211501_P01_WALL-CAVITY-FILL-SIDE-LOWER-LH_CAD (Autodesk Fusion 360 design; units mm, degrees)
part number: 2026-11-01-01-09-27-023
description: WALL - CAVITY FILL - SIDE LOWER - LH | Vách trái - bông PET dưới | P01
part number: 211501
Autodesk Fusion 360 part; units mm, degrees
ref_plane "WorkPlane1" through (0, 0, 132.26) normal (0, 0, 1) x (1, 0, 0) in component "211501 WALL - CAVITY FILL - SIDE LOWER - LH"
sketch "SKETCH - FILL BAY 1" plane through (0, 0, 132.26) normal (0, 0, 1) x (1, 0, 0) in component "211501 WALL - CAVITY FILL - SIDE LOWER - LH"
  line L0 (-1244, -622.74) -> (-1204, -622.74)
  line L1 (-1204, -622.74) -> (-1204, -277.805)
  line L2 (-1204, -277.805) -> (-1244, -277.805)
  line L3 (-1244, -277.805) -> (-1244, -622.74)
  dimension "d167" = 40
  dimension "d168" = 344.935
  dimension "d169" = 1244
  dimension "d170" = 622.74
  constraint horizontal L0
  constraint vertical L1
  constraint horizontal L2
  constraint vertical L3
  measures "d167" horizontal distance of L0.start L0.end
  measures "d168" vertical distance of L0.start L2.end
  measures "d169" horizontal distance of origin L0.start
  measures "d170" vertical distance of origin L0.start
extrude "EXTRUDE - FILL BAY 1" add sketch "SKETCH - FILL BAY 1" along normal blind 1102.74 makes body 1 in component "211501 WALL - CAVITY FILL - SIDE LOWER - LH"
pattern_linear "PATTERN - FILL BAYS" count 3 spacing 364.935 along (0, 1, 0) of bodies 1 makes body 2 at (-1244, -27.8483, 499.84) makes body 3 at (-1244, 337.0867, 499.84) in component "211501 WALL - CAVITY FILL - SIDE LOWER - LH"
ref_plane "WorkPlane2" through (0, 0, 132.26) normal (0, 0, 1) x (1, 0, 0) in component "211501 WALL - CAVITY FILL - SIDE LOWER - LH"
sketch "SKETCH - FILL BAY LAST" plane through (0, 0, 132.26) normal (0, 0, 1) x (1, 0, 0) in component "211501 WALL - CAVITY FILL - SIDE LOWER - LH"
  line L0 (-1244, 472.065) -> (-1204, 472.065)
  line L1 (-1204, 472.065) -> (-1204, 807)
  line L2 (-1204, 807) -> (-1244, 807)
  line L3 (-1244, 807) -> (-1244, 472.065)
  dimension "d179" = 40
  dimension "d180" = 334.935
  dimension "d181" = 1244
  dimension "d182" = 472.065
  constraint horizontal L0
  constraint vertical L1
  constraint horizontal L2
  constraint vertical L3
  measures "d179" horizontal distance of L0.start L0.end
  measures "d180" vertical distance of L0.start L2.end
  measures "d181" horizontal distance of origin L0.start
  measures "d182" vertical distance of origin L0.start
extrude "EXTRUDE - FILL BAY LAST" add sketch "SKETCH - FILL BAY LAST" along normal blind 1102.74 separate body makes body 4 in component "211501 WALL - CAVITY FILL - SIDE LOWER - LH"
ref_plane "WorkPlane3" through (0, 0, 132.26) normal (0, 0, 1) x (1, 0, 0) in component "211501 WALL - CAVITY FILL - SIDE LOWER - LH"
sketch "SKETCH - FILL POCKET BOTTOM BOLT 1" plane through (0, 0, 132.26) normal (0, 0, 1) x (1, 0, 0) in component "211501 WALL - CAVITY FILL - SIDE LOWER - LH"
  line L0 (-1244, -452.74) -> (-1204, -452.74)
  line L1 (-1204, -452.74) -> (-1204, -392.74)
  line L2 (-1204, -392.74) -> (-1244, -392.74)
  line L3 (-1244, -392.74) -> (-1244, -452.74)
  dimension "d187" = 40
  dimension "d188" = 60
  dimension "d189" = 1244
  dimension "d190" = 452.74
  constraint horizontal L0
  constraint vertical L1
  constraint horizontal L2
  constraint vertical L3
  measures "d187" horizontal distance of L0.start L0.end
  measures "d188" vertical distance of L0.start L2.end
  measures "d189" horizontal distance of origin L0.start
  measures "d190" vertical distance of origin L0.start
extrude "CUT - FILL POCKET BOTTOM BOLT 1" cut sketch "SKETCH - FILL POCKET BOTTOM BOLT 1" along normal blind 60 bodies 1 in component "211501 WALL - CAVITY FILL - SIDE LOWER - LH"
ref_plane "WorkPlane4" through (0, 0, 132.26) normal (0, 0, 1) x (1, 0, 0) in component "211501 WALL - CAVITY FILL - SIDE LOWER - LH"
sketch "SKETCH - FILL POCKET BOTTOM BOLT 2" plane through (0, 0, 132.26) normal (0, 0, 1) x (1, 0, 0) in component "211501 WALL - CAVITY FILL - SIDE LOWER - LH"
  line L0 (-1244, -101.8267) -> (-1204, -101.8267)
  line L1 (-1204, -101.8267) -> (-1204, -41.8267)
  line L2 (-1204, -41.8267) -> (-1244, -41.8267)
  line L3 (-1244, -41.8267) -> (-1244, -101.8267)
  dimension "d195" = 40
  dimension "d196" = 60
  dimension "d197" = 1244
  dimension "d198" = 101.8267
  constraint horizontal L0
  constraint vertical L1
  constraint horizontal L2
  constraint vertical L3
  measures "d195" horizontal distance of L0.start L0.end
  measures "d196" vertical distance of L0.start L2.end
  measures "d197" horizontal distance of origin L0.start
  measures "d198" vertical distance of origin L0.start
extrude "CUT - FILL POCKET BOTTOM BOLT 2" cut sketch "SKETCH - FILL POCKET BOTTOM BOLT 2" along normal blind 60 bodies 2 in component "211501 WALL - CAVITY FILL - SIDE LOWER - LH"
ref_plane "WorkPlane5" through (0, 0, 132.26) normal (0, 0, 1) x (1, 0, 0) in component "211501 WALL - CAVITY FILL - SIDE LOWER - LH"
sketch "SKETCH - FILL POCKET BOTTOM BOLT 3" plane through (0, 0, 132.26) normal (0, 0, 1) x (1, 0, 0) in component "211501 WALL - CAVITY FILL - SIDE LOWER - LH"
  line L0 (-1244, 249.0867) -> (-1204, 249.0867)
  line L1 (-1204, 249.0867) -> (-1204, 309.0867)
  line L2 (-1204, 309.0867) -> (-1244, 309.0867)
  line L3 (-1244, 309.0867) -> (-1244, 249.0867)
  dimension "d203" = 40
  dimension "d204" = 60
  dimension "d205" = 1244
  dimension "d206" = 249.0867
  constraint horizontal L0
  constraint vertical L1
  constraint horizontal L2
  constraint vertical L3
  measures "d203" horizontal distance of L0.start L0.end
  measures "d204" vertical distance of L0.start L2.end
  measures "d205" horizontal distance of origin L0.start
  measures "d206" vertical distance of origin L0.start
extrude "CUT - FILL POCKET BOTTOM BOLT 3" cut sketch "SKETCH - FILL POCKET BOTTOM BOLT 3" along normal blind 60 bodies 3 in component "211501 WALL - CAVITY FILL - SIDE LOWER - LH"
ref_plane "WorkPlane6" through (0, 0, 132.26) normal (0, 0, 1) x (1, 0, 0) in component "211501 WALL - CAVITY FILL - SIDE LOWER - LH"
sketch "SKETCH - FILL POCKET BOTTOM BOLT 4" plane through (0, 0, 132.26) normal (0, 0, 1) x (1, 0, 0) in component "211501 WALL - CAVITY FILL - SIDE LOWER - LH"
  line L0 (-1244, 600) -> (-1204, 600)
  line L1 (-1204, 600) -> (-1204, 660)
  line L2 (-1204, 660) -> (-1244, 660)
  line L3 (-1244, 660) -> (-1244, 600)
  dimension "d211" = 40
  dimension "d212" = 60
  dimension "d213" = 1244
  dimension "d214" = 600
  constraint horizontal L0
  constraint vertical L1
  constraint horizontal L2
  constraint vertical L3
  measures "d211" horizontal distance of L0.start L0.end
  measures "d212" vertical distance of L0.start L2.end
  measures "d213" horizontal distance of origin L0.start
  measures "d214" vertical distance of origin L0.start
extrude "CUT - FILL POCKET BOTTOM BOLT 4" cut sketch "SKETCH - FILL POCKET BOTTOM BOLT 4" along normal blind 60 bodies 4 in component "211501 WALL - CAVITY FILL - SIDE LOWER - LH"
ref_plane "WorkPlane7" through (0, 0, 302.26) normal (0, 0, 1) x (1, 0, 0) in component "211501 WALL - CAVITY FILL - SIDE LOWER - LH"
sketch "SKETCH - FILL POCKET DECOR BOLT 1" plane through (0, 0, 302.26) normal (0, 0, 1) x (1, 0, 0) in component "211501 WALL - CAVITY FILL - SIDE LOWER - LH"
  line L0 (-1244, -622.74) -> (-1204, -622.74)
  line L1 (-1204, -622.74) -> (-1204, -562.74)
  line L2 (-1204, -562.74) -> (-1244, -562.74)
  line L3 (-1244, -562.74) -> (-1244, -622.74)
  dimension "d219" = 40
  dimension "d220" = 60
  dimension "d221" = 1244
  dimension "d222" = 622.74
  constraint horizontal L0
  constraint vertical L1
  constraint horizontal L2
  constraint vertical L3
  measures "d219" horizontal distance of L0.start L0.end
  measures "d220" vertical distance of L0.start L2.end
  measures "d221" horizontal distance of origin L0.start
  measures "d222" vertical distance of origin L0.start
extrude "CUT - FILL POCKET DECOR BOLT 1" cut sketch "SKETCH - FILL POCKET DECOR BOLT 1" along normal blind 60 bodies 1 in component "211501 WALL - CAVITY FILL - SIDE LOWER - LH"
ref_plane "WorkPlane8" through (0, 0, 653.63) normal (0, 0, 1) x (1, 0, 0) in component "211501 WALL - CAVITY FILL - SIDE LOWER - LH"
sketch "SKETCH - FILL POCKET DECOR BOLT 2" plane through (0, 0, 653.63) normal (0, 0, 1) x (1, 0, 0) in component "211501 WALL - CAVITY FILL - SIDE LOWER - LH"
  line L0 (-1244, -622.74) -> (-1204, -622.74)
  line L1 (-1204, -622.74) -> (-1204, -562.74)
  line L2 (-1204, -562.74) -> (-1244, -562.74)
  line L3 (-1244, -562.74) -> (-1244, -622.74)
  dimension "d227" = 40
  dimension "d228" = 60
  dimension "d229" = 1244
  dimension "d230" = 622.74
  constraint horizontal L0
  constraint vertical L1
  constraint horizontal L2
  constraint vertical L3
  measures "d227" horizontal distance of L0.start L0.end
  measures "d228" vertical distance of L0.start L2.end
  measures "d229" horizontal distance of origin L0.start
  measures "d230" vertical distance of origin L0.start
extrude "CUT - FILL POCKET DECOR BOLT 2" cut sketch "SKETCH - FILL POCKET DECOR BOLT 2" along normal blind 60 bodies 1 in component "211501 WALL - CAVITY FILL - SIDE LOWER - LH"
ref_plane "WorkPlane9" through (0, 0, 1005) normal (0, 0, 1) x (1, 0, 0) in component "211501 WALL - CAVITY FILL - SIDE LOWER - LH"
sketch "SKETCH - FILL POCKET DECOR BOLT 3" plane through (0, 0, 1005) normal (0, 0, 1) x (1, 0, 0) in component "211501 WALL - CAVITY FILL - SIDE LOWER - LH"
  line L0 (-1244, -622.74) -> (-1204, -622.74)
  line L1 (-1204, -622.74) -> (-1204, -562.74)
  line L2 (-1204, -562.74) -> (-1244, -562.74)
  line L3 (-1244, -562.74) -> (-1244, -622.74)
  dimension "d235" = 40
  dimension "d236" = 60
  dimension "d237" = 1244
  dimension "d238" = 622.74
  constraint horizontal L0
  constraint vertical L1
  constraint horizontal L2
  constraint vertical L3
  measures "d235" horizontal distance of L0.start L0.end
  measures "d236" vertical distance of L0.start L2.end
  measures "d237" horizontal distance of origin L0.start
  measures "d238" vertical distance of origin L0.start
extrude "CUT - FILL POCKET DECOR BOLT 3" cut sketch "SKETCH - FILL POCKET DECOR BOLT 3" along normal blind 60 bodies 1 in component "211501 WALL - CAVITY FILL - SIDE LOWER - LH"
component "211501 WALL - CAVITY FILL - SIDE LOWER - LH" placed x (1, 0, 0) y (0, 1, 0) z (0, 0, 1) at (0, 0, 0)
equation "pod_w_Ref = 2500 mm" comment "DECIDED: D-01; conventions s4 (X = +-1250)"
equation "pod_d_Ref = 1700 mm" comment "DECIDED: D-01; conventions s4 (Y = +-850)"
equation "pod_h_Ref = 2400 mm" comment "DECIDED: D-21 (room floor to roof skin top)"
equation "glide_h_Ref = 10 mm" comment "ASSUMPTION: layout study inputs.py glide_h"
equation "band_h_Ref = 100 mm" comment "SOURCE: layout study B1 list B-BAND 100x40; inputs.py base_h"
equation "outer_t_Ref = skin_t_Ref + bond_t_Ref + frame_t_Ref" comment "DECIDED: PM ruling 2026-10-31: ACP 3 + bond line 3 + frame 40, walls and ceiling (was 43)"
equation "cav_gap_Ref = 4 mm" comment "DECIDED: D-16, D-42: the gap between the outer panel and the lining cassette in the wall and ceiling stack"
equation "cass_t_Ref = 34 mm" comment "SOURCE: layout study B1 final list L-CASS 34 (tray + 25 gap + felt 9)"
equation "stack_t_Ref = outer_t_Ref + cav_gap_Ref + cass_t_Ref" comment "CALCULATION: D-16, D-42 stack, walls and ceiling: outer panel + cavity gap + cassette (PM ruling 2026-10-31 on outer_t)"
equation "wall_depth_Ref = 1495 mm" comment "DECIDED: PM ruling pass C: side walls start at the decor back plate (Y -645), as v1 (1496)"
equation "lin_gap_Ref = 4 mm" comment "ASSUMPTION: PM ruling pass C: gap above the upper side linings so they stay floating (= the 4 mm stack gap)"
equation "seam_gap_Ref = 2.26 mm" comment "DECIDED: PM ruling 2026-10-31 (Mechanical Checker F-001, F-005): the Joints Engineer's 2.26 mm at all nine site seam types, set by a metal stop (1.5 stop washer + 0.76 rivnut head; joints register section 2.8)"
equation "wall_z0_Ref = glide_h_Ref + band_h_Ref" comment "CALCULATION: base band top: glides + band"
equation "panel_z0_Ref = wall_z0_Ref + seam_gap_Ref" comment "CALCULATION: walls stand one seam_gap above the band top (joints register 2.8, IF-01)"
equation "wall_h_Ref = pod_h_Ref - wall_z0_Ref" comment "CALCULATION: 2290 = layout study v2_model wall_h"
equation "side_h_Ref = ( wall_h_Ref - 2 * seam_gap_Ref ) / 2" comment "CALCULATION: D-23: 2 sheets per side wall; the gap on the band and the horizontal seam (joints register 2.8)"
equation "back_oh_Ref = pod_h_Ref - outer_t_Ref - seam_gap_Ref - panel_z0_Ref" comment "CALCULATION: PM ruling 2026-10-31 (pass D, F-004): the back outer frames run up to the ceiling frame (pod_h - outer_t), less the seam_gap under it, closing the slot at the back top edge"
equation "back_ph_Ref = ( back_oh_Ref - seam_gap_Ref ) / 2" comment "CALCULATION: D-23: 4 sheets on the back, two equal rows with one seam_gap between them (joints register 2.8); the lower back linings match the lower row, as on the side walls"
equation "n_base_bolt_Ref = 4" comment "DECIDED: PM ruling 2026-10-31, J-BASE-01: bolts per panel along the band, evenly spaced"
equation "skin_t_Ref = 3 mm" comment "DECIDED: ACP skin, walls and ceiling (D-16; PM ruling 2026-10-31 on outer_t)"
equation "bond_t_Ref = 3 mm" comment "DECIDED: bond line between the ACP and the frame (PM ruling 2026-10-31 on outer_t)"
equation "frame_t_Ref = 40 mm" comment "DECIDED: aluminium frame tube depth, walls and ceiling (PM ruling 2026-10-31 on outer_t)"
equation "bolt_edge_inset_Ref = 220 mm" comment "DECIDED: PM ruling 2026-10-31: on every bolted edge the end bolts sit this far in from each panel end (the FRAME end, where the bolts go), the rest evenly spaced"
equation "spigot_inset_Ref = 100 mm" comment "DECIDED: PM ruling 2026-10-31: locating spigots this far in from each panel end (round hole at one end, slot at the other)"
equation "ceil_bolt_z_Ref = pod_h_Ref - outer_t_Ref + frame_t_Ref / 2" comment "DECIDED: PM ruling 2026-10-31, J-CEIL-01 wall to ceiling: the bolt line on the ceiling frame's centre (Z 2374)"
equation "pod_w = pod_w_Ref" comment "LINKED: pod_w_Ref, derived from 100000_P04_POD-SKELETON_CAD v4 (skeleton is the single source)"
equation "pod_d = pod_d_Ref" comment "LINKED: pod_d_Ref, derived from 100000_P04_POD-SKELETON_CAD v4 (skeleton is the single source)"
equation "pod_h = pod_h_Ref" comment "LINKED: pod_h_Ref, derived from 100000_P04_POD-SKELETON_CAD v4 (skeleton is the single source)"
equation "wall_depth = wall_depth_Ref" comment "LINKED: wall_depth_Ref, derived from 100000_P04_POD-SKELETON_CAD v4 (skeleton is the single source)"
equation "wall_z0 = wall_z0_Ref" comment "LINKED: wall_z0_Ref, derived from 100000_P04_POD-SKELETON_CAD v4 (skeleton is the single source)"
equation "panel_z0 = panel_z0_Ref" comment "LINKED: panel_z0_Ref, derived from 100000_P04_POD-SKELETON_CAD v4 (skeleton is the single source)"
equation "side_h = side_h_Ref" comment "LINKED: side_h_Ref, derived from 100000_P04_POD-SKELETON_CAD v4 (skeleton is the single source)"
equation "back_ph = back_ph_Ref" comment "LINKED: back_ph_Ref, derived from 100000_P04_POD-SKELETON_CAD v4 (skeleton is the single source)"
equation "stack_t = stack_t_Ref" comment "LINKED: stack_t_Ref, derived from 100000_P04_POD-SKELETON_CAD v4 (skeleton is the single source)"
equation "outer_t = outer_t_Ref" comment "LINKED: outer_t_Ref, derived from 100000_P04_POD-SKELETON_CAD v4 (skeleton is the single source)"
equation "cass_t = cass_t_Ref" comment "LINKED: cass_t_Ref, derived from 100000_P04_POD-SKELETON_CAD v4 (skeleton is the single source)"
equation "lin_gap = lin_gap_Ref" comment "LINKED: lin_gap_Ref, derived from 100000_P04_POD-SKELETON_CAD v4 (skeleton is the single source)"
equation "seam_gap = seam_gap_Ref" comment "LINKED: seam_gap_Ref, derived from 100000_P04_POD-SKELETON_CAD v4 (skeleton is the single source)"
equation "skin_t = skin_t_Ref" comment "LINKED: skin_t_Ref, derived from 100000_P04_POD-SKELETON_CAD v4 (skeleton is the single source)"
equation "bond_t = bond_t_Ref" comment "LINKED: bond_t_Ref, derived from 100000_P04_POD-SKELETON_CAD v4 (skeleton is the single source)"
equation "bolt_edge_inset = bolt_edge_inset_Ref" comment "LINKED: bolt_edge_inset_Ref, derived from 100000_P04_POD-SKELETON_CAD v4 (skeleton is the single source)"
equation "spigot_inset = spigot_inset_Ref" comment "LINKED: spigot_inset_Ref, derived from 100000_P04_POD-SKELETON_CAD v4 (skeleton is the single source)"
equation "n_base_bolt = n_base_bolt_Ref" comment "LINKED: n_base_bolt_Ref, derived from 100000_P04_POD-SKELETON_CAD v4 (skeleton is the single source)"
equation "ceil_bolt_z = ceil_bolt_z_Ref" comment "LINKED: ceil_bolt_z_Ref, derived from 100000_P04_POD-SKELETON_CAD v4 (skeleton is the single source)"
equation "tube_w = 20 mm" comment "CONFIRMED: D-34, D-54: aluminium tube 20 x 40 x 1.2; the 20 mm face carries the skin, so the 40 mm runs through the wall (outer_t = ACP 3 + frame 40). The joint register may turn it for the bond width (HOLD)"
equation "tube_d = outer_t - skin_t - bond_t" comment "CALCULATION: frame depth = outer panel 46 - skin 3 - bond 3 = 40 (D-34)"
equation "tube_t = 1.2 mm" comment "CONFIRMED: D-34, D-54, D-85: perimeter members (rails, front and back stiles) keep the 1.2 mm wall; they carry the rivnuts (grip check passed)"
equation "stud_t = 1.0 mm" comment "CONFIRMED: D-85 (weight): intermediate studs at a 1.0 mm wall; they carry no rivnut, only the skin's bond line"
equation "stile_pitch_max = 400 mm" comment "CONFIRMED: D-16, D-34: members 400 mm apart or less, to keep the ACP flat"
equation "pnl_len = wall_depth - seam_gap" comment "CALCULATION: D-49 depth 1495 less the 2.26 gap at the decor back plate (PM ruling on F-008): 1492.74"
equation "pnl_h = side_h" comment "CALCULATION: skeleton side_h: 2 sheets per side wall (D-23) with the seam gaps"
equation "skin_ret = outer_t - skin_t" comment "ASSUMPTION: back return of the side skin: covers the frame's back end at the corner, where the side skin covers the back panel's edge (D-55; sample drawing D04). V-groove and fold per the ACP maker (HOLD H16)"
equation "skin_setback = 0 mm" comment "ASSUMPTION: skin edge set back from the frame's top and bottom edges: 0, so the outside reveal equals the 2.26 seam gap (D-23: crisp, aligned reveals; joints register 2.8 leaves the setback to the WALL drawing)"
equation "frm_len = pnl_len - skin_t" comment "CALCULATION: the frame stops at the inside of the skin's back return"
equation "frm_h = pnl_h" comment "ASSUMPTION: the frame fills the skeleton envelope height; seam and base gasket gaps are set by the joint register (HOLD)"
equation "corner_w = 40 mm" comment "CONFIRMED: the side panel's back member is 40 x 40 x 1.2 (PM ruling on the joints register, item 3, 2026-10-31; register F2, FR-06): the back corner joint needs a 37+ mm overlap for the rivnut and the bolt"
equation "stile_n_mid = ceil(( frm_len - tube_w / 2 - corner_w / 2 ) / stile_pitch_max) - 1" comment "CALCULATION: intermediate stiles so that no stile pitch (centre to centre) exceeds stile_pitch_max"
equation "stile_pitch = ( frm_len - tube_w / 2 - corner_w / 2 ) / ( stile_n_mid + 1 )" comment "CALCULATION: equal stile pitch, centre to centre, from the front stile to the 40 mm back stile"
equation "top_h = tube_w" comment "CALCULATION: top member height: 20 on a lower panel; 40 x 40 on an upper panel, where the ceiling bolts in (PM ruling R-J3, joints register FR-06)"
equation "stile_len = frm_h - tube_w - top_h" comment "CALCULATION: stiles fit between the full-length rails (butt joints)"
equation "ceil_bolt_dz = pod_h - ceil_bolt_z" comment "CALCULATION: J-CEIL-01 side bolts on the ceiling frame tube's centre: the skeleton's ceil_bolt_z, Z 2374 on P04 (joints register R-J15, FR-07)"
equation "fill_t = tube_d" comment "CALCULATION: 40 mm PET fill fills the frame depth (D-34; layout study 40 mm)"
equation "bolt_d = 7 mm" comment "CONFIRMED: PM ruling on F-009: bolt holes 7.0 (0.51 float), position tolerance 0.4 (+-0.2) from the spigot hole, CNC or drill jig (joints register FR-02)"
equation "access_d = 19 mm" comment "CALCULATION: register FR-03: passes the 18 mm head washer (ISO 7093-1, R-J10), the M6 head and the 5 mm key; holds the grommet retainer (H-02)"
equation "bolt_line_y = pod_d / 2 - skin_t - bond_t - tube_d / 2" comment "CONFIRMED: J-WALL-02 bolt line on the back panel's tube centre, Y 824 (joints register R-J15, FR-07)"
equation "rivnut_d = 9.53 mm" comment "SOURCE: Sherex CAH3-610-4.2 hole 9.53 +0.10 (HW-SEL A5; register H-03)"
equation "spigot_d = 8.5 mm" comment "ASSUMPTION: register FR-05: hole for the 8 mm locating spigot H-05"
equation "spigot_slot = 14 mm" comment "ASSUMPTION: register FR-05: slot length for the second spigot"
equation "spigot_edge = spigot_inset" comment "CALCULATION: the skeleton's spigot_inset: spigots 100 from each end of the edge (PM ruling 2026-10-31, R-J13)"
equation "bolt_edge = bolt_edge_inset" comment "CALCULATION: the skeleton's bolt_edge_inset: end bolts 220 in from the panel's ends, evenly spaced, every bolt 30 or more from any stile (PM ruling 2026-10-31, R-J14)"
equation "n_side_jnt = 3" comment "SOURCE: register J-WALL-02, J-FRONT-01: 3 bolts up each side panel"
equation "side_jnt_pitch = ( pnl_h - 2 * bolt_edge ) / ( n_side_jnt - 1 )" comment "CALCULATION: equal pitch of the 3 bolts up the corner and decor joints"
equation "pocket_w = 60 mm" comment "ASSUMPTION: register FR-10: fill left out 60 x 60 next to each bolt for the key"
equation "corner_z0 = panel_z0" comment "CALCULATION: bottom of the back panel row this side panel meets at the corner (B1/B2 or B3/B4, skeleton P04)"
equation "corner_bolt_pitch = ( back_ph - 2 * bolt_edge ) / ( n_side_jnt - 1 )" comment "CALCULATION: J-WALL-02 bolts run along the back panel's edge: 220, 559.31, 898.61 on its 1118.61 (joints register 2.9)"
equation "n_len_bolt = n_base_bolt" comment "CALCULATION: the skeleton's n_base_bolt (4): the same count on J-WALL-01 and the J-CEIL-01 side edges (register 2.9)"
equation "ceil_bolt_pitch = ( wall_depth - 2 * bolt_edge ) / ( n_len_bolt - 1 )" comment "CALCULATION: J-CEIL-01 side edge: 4 bolts along the ceiling's 1495 from Y -645 (its front edge), 220 rule, pitch 351.67 on P04; CEILING drills the same (PM ruling 2026-10-31 16:55; joints register 2.9)"
equation "len_bolt_pitch = ( pnl_len - 2 * bolt_edge ) / ( n_len_bolt - 1 )" comment "CALCULATION: even pitch of the bolts along the panel"
equation "felt_t = 9 mm" comment "SOURCE: plan VT03-PET 9 mm PET felt; HW-SEL A3; D-31 (the factory's felt)"
equation "tray_t = 0.5 mm" comment "CONFIRMED: D-37: galvanised steel tray 0.5 mm"
equation "tray_h = cass_t" comment "CONFIRMED: PM ruling 2026-10-31 (WALL group, option 1): the wall cassettes use the ceiling's tray, returns the full cassette depth (34) turned in as lips that hold the felt, no ribs; settles H09 for the walls"
equation "lip_w = 12 mm" comment "CONFIRMED: PM ruling 2026-10-31 (WALL group, option 1): 12 mm lips hold the felt edge"
equation "bend_r = tray_t" comment "ASSUMPTION: inside bend radius 1 x t for 0.5 mm DX51D (the sheet metal rule's bend radius is its Thickness); the factory's tooling sets it (guideline 9)"
equation "felt_c = 1 mm" comment "ASSUMPTION: felt edge clearance inside the returns, as the ceiling cassette"
equation "gap_h = tray_h - felt_t - 2 * tray_t" comment "CALCULATION: air gap between the tray base and the felt (24): the acoustic gap (D-17) and the cable path (D-26)"
equation "cass_len = wall_depth - stack_t + cass_t" comment "CALCULATION: = 1448: from the decor back plate to past the back cassette's face, closing the inside corner (D-57)"
equation "cass_h = side_h" comment "CALCULATION: lower: the panel height; upper: stops lin_gap under the roof frame so it floats (D-57)"
equation "clip_zone_h = 60 mm" comment "ASSUMPTION: height of each reserved clip zone (H03: no clip named)"
equation "clip_zone_dz = 100 mm" comment "ASSUMPTION: clip zone centre from the cassette's top and bottom edges (H03)"
equation "stopw_od = 20 mm" comment "SOURCE: joints register H-08: stop washer Ø10.5 x Ø20 x 1.5 (PROPOSED part)"
equation "stopw_id = 10.5 mm" comment "SOURCE: joints register H-08"
equation "stopw_t = 1.5 mm" comment "SOURCE: joints register H-08: rivnut head 0.76 + washer 1.5 = the 2.26 stop (R-J5)"
equation "rivnut_head_d = 12.96 mm" comment "SOURCE: Sherex CAH3-610-4.2 head Ø12.96 (joints register H-03, SHX)"
equation "rivnut_head_t = 0.76 mm" comment "SOURCE: Sherex CAH3-610-4.2 head 0.76 ±0.08 (H-03, SHX)"
equation "rivnut_body_d = 9.5 mm" comment "SOURCE: Sherex CAH3-610-4.2 body Ø9.50 max (H-03, SHX)"
equation "rivnut_len = 10.16 mm" comment "SOURCE: Sherex CAH3-610-4.2 installed length 10.16 max under the head (H-03, SHX); the bulge inside the tube is not modelled"
equation "m6_d = 6 mm" comment "CALCULATION: M6 threads shown at their 6 mm major diameter (no modelled thread)"
equation "spigot_pin_d = 8 mm" comment "SOURCE: joints register H-05: Ø8 stainless pin (PROPOSED, assumption sizes)"
equation "spigot_proud = 8 mm" comment "SOURCE: joints register H-05: stands 8 proud (read as: of the joint face)"
equation "spigot_thread_l = 10 mm" comment "ASSUMPTION: M6 thread into the spigot rivnut; H-05 gives no length; 10 stays inside the rivnut's 10.16"
equation "d165 = ( panel_z0 ) + tube_w"
equation "d167 = ( -( pod_w / 2 - outer_t ) ) - ( -( pod_w / 2 - skin_t - bond_t ) )"
equation "d168 = ( ( pod_d / 2 - wall_depth + seam_gap ) + stile_pitch ) - ( ( pod_d / 2 - wall_depth + seam_gap ) + tube_w )"
equation "d169 = abs(-( pod_w / 2 - skin_t - bond_t ))"
equation "d170 = abs(( pod_d / 2 - wall_depth + seam_gap ) + tube_w)"
equation "d171 = ( ( panel_z0 + side_h ) - top_h ) - ( ( panel_z0 ) + tube_w )"
equation "d173 = stile_n_mid"
equation "d175 = stile_pitch"
equation "d177 = ( panel_z0 ) + tube_w"
equation "d179 = ( -( pod_w / 2 - outer_t ) ) - ( -( pod_w / 2 - skin_t - bond_t ) )"
equation "d180 = ( ( pod_d / 2 - skin_t ) - corner_w ) - ( ( pod_d / 2 - wall_depth + seam_gap ) + stile_n_mid * stile_pitch + tube_w )"
equation "d181 = abs(-( pod_w / 2 - skin_t - bond_t ))"
equation "d182 = abs(( pod_d / 2 - wall_depth + seam_gap ) + stile_n_mid * stile_pitch + tube_w)"
equation "d183 = ( ( panel_z0 + side_h ) - top_h ) - ( ( panel_z0 ) + tube_w )"
equation "d185 = ( panel_z0 ) + tube_w"
equation "d187 = ( -( pod_w / 2 - outer_t ) ) - ( -( pod_w / 2 - skin_t - bond_t ) )"
equation "d188 = ( ( ( pod_d / 2 - wall_depth + seam_gap ) + bolt_edge + 0 * len_bolt_pitch ) + pocket_w / 2 ) - ( ( ( pod_d / 2 - wall_depth + seam_gap ) + bolt_edge + 0 * len_bolt_pitch ) - pocket_w / 2 )"
equation "d189 = abs(-( pod_w / 2 - skin_t - bond_t ))"
equation "d190 = abs(( ( pod_d / 2 - wall_depth + seam_gap ) + bolt_edge + 0 * len_bolt_pitch ) - pocket_w / 2)"
equation "d191 = ( ( ( panel_z0 ) + tube_w ) + pocket_w ) - ( ( panel_z0 ) + tube_w )"
equation "d193 = ( panel_z0 ) + tube_w"
equation "d195 = ( -( pod_w / 2 - outer_t ) ) - ( -( pod_w / 2 - skin_t - bond_t ) )"
equation "d196 = ( ( ( pod_d / 2 - wall_depth + seam_gap ) + bolt_edge + 1 * len_bolt_pitch ) + pocket_w / 2 ) - ( ( ( pod_d / 2 - wall_depth + seam_gap ) + bolt_edge + 1 * len_bolt_pitch ) - pocket_w / 2 )"
equation "d197 = abs(-( pod_w / 2 - skin_t - bond_t ))"
equation "d198 = abs(( ( pod_d / 2 - wall_depth + seam_gap ) + bolt_edge + 1 * len_bolt_pitch ) - pocket_w / 2)"
equation "d199 = ( ( ( panel_z0 ) + tube_w ) + pocket_w ) - ( ( panel_z0 ) + tube_w )"
equation "d201 = ( panel_z0 ) + tube_w"
equation "d203 = ( -( pod_w / 2 - outer_t ) ) - ( -( pod_w / 2 - skin_t - bond_t ) )"
equation "d204 = ( ( ( pod_d / 2 - wall_depth + seam_gap ) + bolt_edge + 2 * len_bolt_pitch ) + pocket_w / 2 ) - ( ( ( pod_d / 2 - wall_depth + seam_gap ) + bolt_edge + 2 * len_bolt_pitch ) - pocket_w / 2 )"
equation "d205 = abs(-( pod_w / 2 - skin_t - bond_t ))"
equation "d206 = abs(( ( pod_d / 2 - wall_depth + seam_gap ) + bolt_edge + 2 * len_bolt_pitch ) - pocket_w / 2)"
equation "d207 = ( ( ( panel_z0 ) + tube_w ) + pocket_w ) - ( ( panel_z0 ) + tube_w )"
equation "d209 = ( panel_z0 ) + tube_w"
equation "d211 = ( -( pod_w / 2 - outer_t ) ) - ( -( pod_w / 2 - skin_t - bond_t ) )"
equation "d212 = ( ( ( pod_d / 2 - wall_depth + seam_gap ) + bolt_edge + 3 * len_bolt_pitch ) + pocket_w / 2 ) - ( ( ( pod_d / 2 - wall_depth + seam_gap ) + bolt_edge + 3 * len_bolt_pitch ) - pocket_w / 2 )"
equation "d213 = abs(-( pod_w / 2 - skin_t - bond_t ))"
equation "d214 = abs(( ( pod_d / 2 - wall_depth + seam_gap ) + bolt_edge + 3 * len_bolt_pitch ) - pocket_w / 2)"
equation "d215 = ( ( ( panel_z0 ) + tube_w ) + pocket_w ) - ( ( panel_z0 ) + tube_w )"
equation "d217 = ( ( ( panel_z0 ) + bolt_edge ) + 0 * side_jnt_pitch ) - pocket_w / 2"
equation "d219 = ( -( pod_w / 2 - outer_t ) ) - ( -( pod_w / 2 - skin_t - bond_t ) )"
equation "d220 = ( ( pod_d / 2 - wall_depth + seam_gap ) + tube_w + pocket_w ) - ( ( pod_d / 2 - wall_depth + seam_gap ) + tube_w )"
equation "d221 = abs(-( pod_w / 2 - skin_t - bond_t ))"
equation "d222 = abs(( pod_d / 2 - wall_depth + seam_gap ) + tube_w)"
equation "d223 = ( ( ( ( panel_z0 ) + bolt_edge ) + 0 * side_jnt_pitch ) + pocket_w / 2 ) - ( ( ( ( panel_z0 ) + bolt_edge ) + 0 * side_jnt_pitch ) - pocket_w / 2 )"
equation "d225 = ( ( ( panel_z0 ) + bolt_edge ) + 1 * side_jnt_pitch ) - pocket_w / 2"
equation "d227 = ( -( pod_w / 2 - outer_t ) ) - ( -( pod_w / 2 - skin_t - bond_t ) )"
equation "d228 = ( ( pod_d / 2 - wall_depth + seam_gap ) + tube_w + pocket_w ) - ( ( pod_d / 2 - wall_depth + seam_gap ) + tube_w )"
equation "d229 = abs(-( pod_w / 2 - skin_t - bond_t ))"
equation "d230 = abs(( pod_d / 2 - wall_depth + seam_gap ) + tube_w)"
equation "d231 = ( ( ( ( panel_z0 ) + bolt_edge ) + 1 * side_jnt_pitch ) + pocket_w / 2 ) - ( ( ( ( panel_z0 ) + bolt_edge ) + 1 * side_jnt_pitch ) - pocket_w / 2 )"
equation "d233 = ( ( ( panel_z0 ) + bolt_edge ) + 2 * side_jnt_pitch ) - pocket_w / 2"
equation "d235 = ( -( pod_w / 2 - outer_t ) ) - ( -( pod_w / 2 - skin_t - bond_t ) )"
equation "d236 = ( ( pod_d / 2 - wall_depth + seam_gap ) + tube_w + pocket_w ) - ( ( pod_d / 2 - wall_depth + seam_gap ) + tube_w )"
equation "d237 = abs(-( pod_w / 2 - skin_t - bond_t ))"
equation "d238 = abs(( pod_d / 2 - wall_depth + seam_gap ) + tube_w)"
equation "d239 = ( ( ( ( panel_z0 ) + bolt_edge ) + 2 * side_jnt_pitch ) + pocket_w / 2 ) - ( ( ( ( panel_z0 ) + bolt_edge ) + 2 * side_jnt_pitch ) - pocket_w / 2 )"
named bodies: "FILL - BAY 1", "FILL - BAY 2", "FILL - BAY 3", "FILL - BAY 4"
